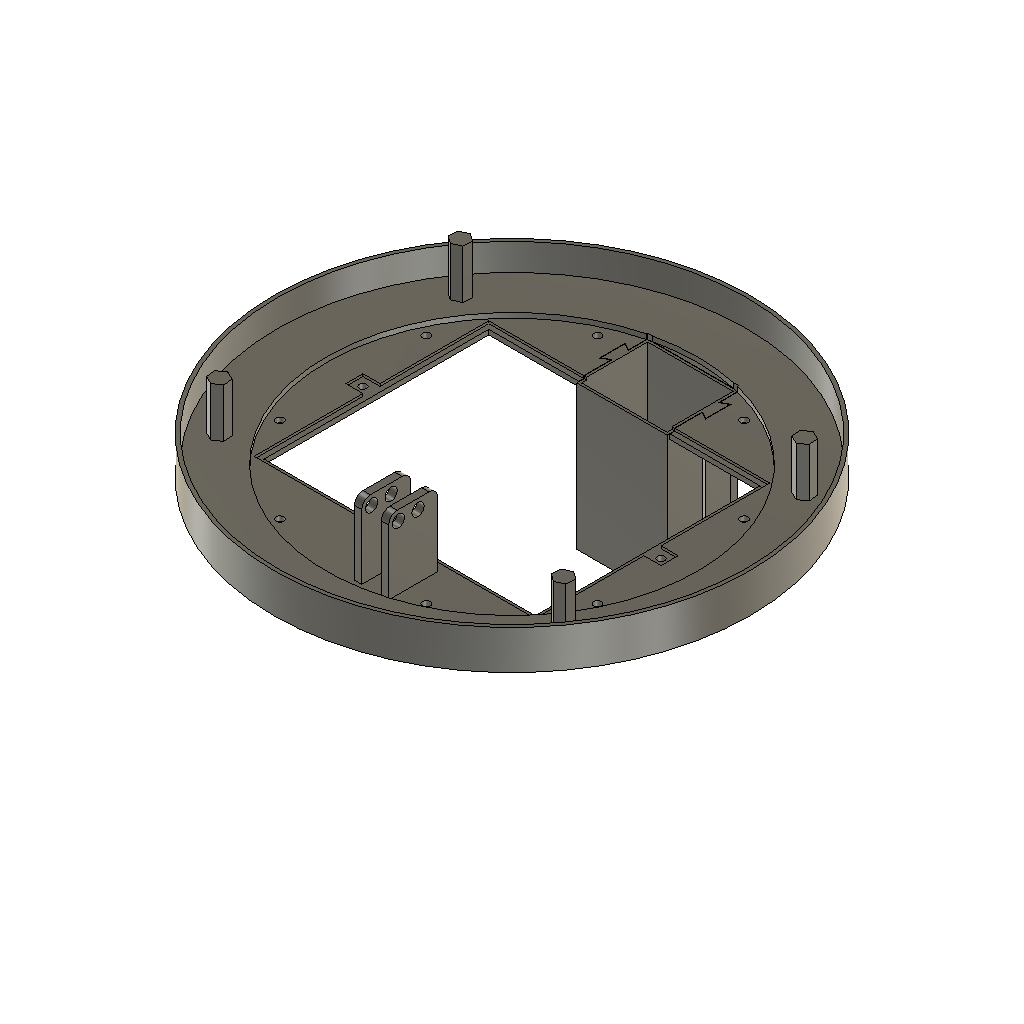
meio soccer (Autodesk Fusion 360 design; units mm, degrees)
part number: 2026-09-15-19-02-09-718
Autodesk Fusion 360 part; units mm, degrees
sketch "Esboço1" plane through (0, 0, 0) normal (0, 0, 1) x (1, 0, 0)
  circle A0 centre (0, 0) radius 97.5
  circle A1 centre (0, 0) radius 96
  circle A2 centre (0, 0) radius 76
  circle A3 centre (0, 0) radius 74.25
  dimension "d1" = 195
  dimension "d2" = 192
  dimension "d3" = 152
  dimension "d4" = 148.5
  constraint coincident A0.centre A1.centre
  constraint concentric A0 A2
  constraint concentric A0 A3
  measures "d1" diameter of A0
  measures "d2" diameter of A1
  measures "d3" diameter of A2
  measures "d4" diameter of A3
extrude "Extrusão1" add sketch "Esboço1" along normal blind 3 contours A0 | A1 | A2 | A3 makes body 1
sketch "Esboço2" plane through (0, 0, 3) normal (0, 0, 1) x (-1, 0, 0)
  circle A0 centre (0, 0) radius 97.5
  circle A1 centre (0, 0) radius 96
  dimension "d24" = 192
  constraint concentric A0 A1
  measures "d24" diameter of A1
extrude "Extrusão2" add sketch "Esboço2" along normal blind 10 bodies 1
sketch "Esboço3" plane through (0, 0, 3) normal (0, 0, 1) x (-1, 0, 0)
  circle A0 centre (0, 0) radius 96
  circle A1 centre (0, 0) radius 75.9595
  circle A2 centre (0, 0) radius 74.25
  dimension "d27" = 151.919
  dimension "d28" = 148.5
  constraint coincident A0.centre A1.centre
  constraint concentric A1 A2
  measures "d27" diameter of A1
  measures "d28" diameter of A2
extrude "Extrusão3" add sketch "Esboço3" along normal blind 10 contours A1 bodies 1
extrude "Extrusão4" add 1 faces at (-88.6796, 8.5431, 3) along direction (0, 0, 1) blind 2 on bodies 1 bodies 1
extrude "Extrusão5" cut 2 faces at (72.8824, 18.5321, 13) (-96.2796, 9.6132, 13) along direction (0, 0, -1) blind 2 on bodies 1 bodies 1
sketch "Esboço8" plane through (0, 0, 3) normal (0, 0, 1) x (-1, 0, 0)
  circle A0 centre (0, 0) radius 74.25
  line L0 (-26, -20.5) -> (26, -20.5)
  line L1 (26, -20.5) -> (26, -62.5)
  line L2 (26, -62.5) -> (-26, -62.5)
  line L3 (-26, -62.5) -> (-26, -20.5)
  dimension "d111" = 52
  dimension "d112" = 42
  constraint horizontal L0
  constraint vertical L1
  constraint horizontal L2
  constraint vertical L3
  measures "d111" distance of L0.start L0.end
  measures "d112" distance of L0.start L2.end
sketch "Esboço9" plane through (0, 0, 3) normal (0, 0, 1) x (-1, 0, 0)
  circle A0 centre (0, 0) radius 74.25
sketch "Esboço13" plane through (0, 0, 0) normal (0, 0, -1) x (1, 0, 0)
  circle A0 centre (0, 0) radius 97.5
  circle A1 centre (-30, 65) radius 1.6
  circle A2 centre (30, 65) radius 1.6
  line L0 (51, -4.42) -> (-51, -4.42)
  line L1 (-51, -4.42) -> (-51, 5.58)
  line L2 (-51, 5.58) -> (51, 5.58)
  line L3 (51, 5.58) -> (51, -4.42)
  line L4 (27.6906, 69) -> (25.3812, 65)
  line L5 (25.3812, 65) -> (27.6906, 61)
  line L6 (27.6906, 61) -> (32.3094, 61)
  line L7 (32.3094, 61) -> (34.6188, 65)
  line L8 (34.6188, 65) -> (32.3094, 69)
  line L9 (32.3094, 69) -> (27.6906, 69)
  line L10 (-32.3094, 69) -> (-34.6188, 65)
  line L11 (-34.6188, 65) -> (-32.3094, 61)
  line L12 (-32.3094, 61) -> (-27.6906, 61)
  line L13 (-27.6906, 61) -> (-25.3812, 65)
  line L14 (-25.3812, 65) -> (-27.6906, 69)
  line L15 (-27.6906, 69) -> (-32.3094, 69)
  line L16 (-61, 27.6906) -> (-61, 32.3094)
  line L17 (-69, 27.6906) -> (-65, 25.3812)
  circle A3 centre (-65, 30) radius 1.6
  line L18 (-61, 32.3094) -> (-65, 34.6188)
  line L19 (-65, 25.3812) -> (-61, 27.6906)
  line L20 (-65, 34.6188) -> (-69, 32.3094)
  line L21 (-69, 32.3094) -> (-69, 27.6906)
  line L22 (-65, -25.3812) -> (-69, -27.6906)
  line L23 (-61, -27.6906) -> (-65, -25.3812)
  line L24 (-61, -32.3094) -> (-61, -27.6906)
  line L25 (-69, -32.3094) -> (-65, -34.6188)
  circle A4 centre (-65, -30) radius 1.6
  line L26 (-69, -27.6906) -> (-69, -32.3094)
  line L27 (-65, -34.6188) -> (-61, -32.3094)
  line L28 (-27.6906, -61) -> (-32.3094, -61)
  line L29 (-27.6906, -69) -> (-25.3812, -65)
  circle A5 centre (-30, -65) radius 1.6
  line L30 (-32.3094, -61) -> (-34.6188, -65)
  line L31 (-25.3812, -65) -> (-27.6906, -61)
  line L32 (-34.6188, -65) -> (-32.3094, -69)
  line L33 (-32.3094, -69) -> (-27.6906, -69)
  line L34 (25.3812, -65) -> (27.6906, -69)
  line L35 (27.6906, -61) -> (25.3812, -65)
  line L36 (32.3094, -61) -> (27.6906, -61)
  line L37 (32.3094, -69) -> (34.6188, -65)
  circle A6 centre (30, -65) radius 1.6
  line L38 (27.6906, -69) -> (32.3094, -69)
  line L39 (34.6188, -65) -> (32.3094, -61)
  line L40 (61, -27.6906) -> (61, -32.3094)
  line L41 (69, -27.6906) -> (65, -25.3812)
  circle A7 centre (65, -30) radius 1.6
  line L42 (61, -32.3094) -> (65, -34.6188)
  line L43 (65, -25.3812) -> (61, -27.6906)
  line L44 (65, -34.6188) -> (69, -32.3094)
  line L45 (69, -32.3094) -> (69, -27.6906)
  line L46 (65, 25.3812) -> (69, 27.6906)
  line L47 (61, 27.6906) -> (65, 25.3812)
  line L48 (61, 32.3094) -> (61, 27.6906)
  line L49 (69, 32.3094) -> (65, 34.6188)
  circle A8 centre (65, 30) radius 1.6
  line L50 (69, 27.6906) -> (69, 32.3094)
  line L51 (65, 34.6188) -> (61, 32.3094)
  point P0 (30, 65)
  point P1 (30, 65)
  point P2 (30, 65)
  point P3 (-30, 65)
  point P4 (-30, 65)
  point P5 (-65, 30)
  point P6 (-65, 30)
  point P7 (-65, 30)
  point P8 (-65, -30)
  point P9 (-65, -30)
  point P10 (-30, -65)
  point P11 (-30, -65)
  point P12 (-30, -65)
  point P13 (30, -65)
  point P14 (30, -65)
  point P15 (65, -30)
  point P16 (65, -30)
  point P17 (65, -30)
  point P18 (65, 30)
  point P19 (65, 30)
  dimension "d163" = 3.2
  dimension "d164" = 3.2
  dimension "d165" = 102
  dimension "d166" = 10
  dimension "d167" = 51
  dimension "d168" = 51
  dimension "d172" = 65
  dimension "d173" = 60
  dimension "d175" = 4
  dimension "d176" = 4
  dimension "d178" = 360
  constraint horizontal L0
  constraint vertical L1
  constraint horizontal L2
  constraint vertical L3
  constraint coincident P2 P1
  constraint coincident P4 P3
  measures "d163" diameter of A1
  measures "d164" diameter of A2
  measures "d165" distance of L0.start L0.end
  measures "d166" distance of L0.start L2.end
  measures "d167" distance of A0.centre L1
  measures "d168" distance of A0.centre L3
  measures "d172" vertical distance of A0.centre P4
  measures "d173" distance of P4 P1
  measures "d175" distance of P2 L9
  measures "d176" distance of P4 L15
extrude "Extrusão14" cut sketch "Esboço13" against normal blind 1 contours L4 L5 L6 L7 L8 L9 | L10 L11 L12 L13 L14 L15 | L16 L17 L18 L19 L20 L21 | L22 L23 L24 L25 L26 L27 | L28 L29 L30 L31 L32 L33 | L34 L35 L36 L37 L38 L39 | L40 L41 L42 L43 L44 L45 | L46 L47 L48 L49 L50 L51 bodies 1
extrude "Extrusão15" cut 8 faces at (64.6384, -29.1944, 0) (30.1948, -64.5727, 0) (-30.2667, -64.861, 0) (-65.4147, -30.52, 0) (-64.6384, 29.1944, 0) (-29.9601, 64.931, 0) (29.8052, 65.4273, 0) (64.6384, 30.8056, 0) along direction (0, 0, 1) blind 45 on bodies 1 bodies 1
sketch "Esboço14" plane through (0, 0, 5) normal (0, 0, 1) x (-1, 0, 0)
  circle A0 centre (0, 0) radius 96
  circle A1 centre (0, 0) radius 75.9595
  circle A2 centre (0, 0) radius 87.5
  circle A3 centre (0, 0) radius 82.5
  line L0 (76.0946, 31.8726) -> (80.7064, 33.8042)
  line L1 (76.0946, -31.8726) -> (80.7064, -33.8042)
  line L2 (65.6498, 49.9636) -> (69.6285, 52.9917)
  line L3 (-65.6498, 49.9636) -> (-69.6285, 52.9917)
  line L4 (-10.4448, 81.8361) -> (-11.0779, 86.7959)
  line L5 (-10.4448, -81.8361) -> (-11.0779, -86.7959)
  line L6 (-65.6498, -49.9636) -> (-69.6285, -52.9917)
  line L7 (10.4448, 81.8361) -> (11.0779, 86.7959)
  line L8 (-76.0946, -31.8726) -> (-80.7064, -33.8042)
  line L9 (-76.0946, 31.8726) -> (-80.7064, 33.8042)
  line L10 (65.6498, -49.9636) -> (69.6285, -52.9917)
  line L11 (10.4448, -81.8361) -> (11.0779, -86.7959)
  dimension "d183" = 175
  dimension "d184" = 165
  dimension "d189" = 360
  dimension "d192" = 360
  constraint coincident A0.centre A1.centre
  constraint coincident A3 L0.start
  constraint coincident A2 L0.end
  constraint perpendicular A2 L0
  constraint coincident A3 L1.start
  constraint coincident A2 L1.end
  constraint perpendicular A2 L1
  constraint coincident A3 L2.start
  constraint coincident A2 L2.end
  constraint perpendicular A2 L2
  constraint coincident A3 L7.start
  constraint coincident A2 L7.end
  constraint perpendicular A2 L7
  measures "d183" diameter of A2
  measures "d184" diameter of A3
sketch "Esboço15" plane through (0, 0, 5) normal (0, 0, 1) x (-1, 0, 0)
  circle A0 centre (0, 0) radius 75.9595
  circle A1 centre (0, 0) radius 96
  line L0 (0, 0) -> (0, 110)
  line L1 (0, 110) -> (0, 0)
  line L2 (0, 0) -> (101.4671, 71.048)
  circle A2 centre (0, 0) radius 86
  line L3 (73.5599, 51.5072) -> (70.1159, 53.1131)
  line L4 (70.1159, 53.1131) -> (67.0031, 50.9335)
  line L5 (67.0031, 50.9335) -> (67.3343, 47.148)
  line L6 (67.3343, 47.148) -> (70.7783, 45.542)
  line L7 (70.7783, 45.542) -> (73.891, 47.7216)
  line L8 (73.891, 47.7216) -> (73.5599, 51.5072)
  line L9 (0, 0) -> (-94.4768, 66.1533)
  line L10 (0, 0) -> (-97.6365, -68.3658)
  line L11 (0, 0) -> (97.99, -68.6133)
  line L12 (0, 0) -> (0, -120)
  line L13 (67.3343, -47.148) -> (67.0031, -50.9335)
  line L14 (67.0031, -50.9335) -> (70.1159, -53.1131)
  line L15 (70.1159, -53.1131) -> (73.5599, -51.5072)
  line L16 (73.5599, -51.5072) -> (73.891, -47.7216)
  line L17 (73.891, -47.7216) -> (70.7783, -45.542)
  line L18 (70.7783, -45.542) -> (67.3343, -47.148)
  line L19 (-67.3343, -47.148) -> (-70.7783, -45.542)
  line L20 (-70.7783, -45.542) -> (-73.891, -47.7216)
  line L21 (-73.891, -47.7216) -> (-73.5599, -51.5072)
  line L22 (-73.5599, -51.5072) -> (-70.1159, -53.1131)
  line L23 (-70.1159, -53.1131) -> (-67.0031, -50.9335)
  line L24 (-67.0031, -50.9335) -> (-67.3343, -47.148)
  line L25 (-67.3343, 47.148) -> (-67.0031, 50.9335)
  line L26 (-67.0031, 50.9335) -> (-70.1159, 53.1131)
  line L27 (-70.1159, 53.1131) -> (-73.5599, 51.5072)
  line L28 (-73.5599, 51.5072) -> (-73.891, 47.7216)
  line L29 (-73.891, 47.7216) -> (-70.7783, 45.542)
  line L30 (-70.7783, 45.542) -> (-67.3343, 47.148)
  point P0 (70.4471, 49.3276)
  point P1 (70.4471, -49.3276)
  point P2 (-70.4471, -49.3276)
  point P3 (-70.4471, 49.3276)
  dimension "d195" = 55
  dimension "d196" = 172
  dimension "d197" = 3.8
  dimension "d198" = 55
  dimension "d199" = 55
  dimension "d200" = 55
  dimension "d201" = 3.8
  dimension "d202" = 3.8
  dimension "d203" = 3.8
  constraint coincident A0.centre A1.centre
  constraint vertical L0
  constraint coincident A2 P0
  constraint coincident L2 P0
  constraint coincident L2 L3.start
  constraint vertical L12
  constraint coincident L11 P1
  constraint coincident A2 P1
  constraint coincident A2 P2
  constraint coincident L10 P2
  constraint coincident A2 P3
  constraint coincident L9 P3
  measures "d195" angle of L0 L2
  measures "d196" diameter of A2
  measures "d197" distance of L3.start P0
  measures "d198" angle of L1 L9
  measures "d199" angle of L11 L12
  measures "d200" angle of L10 L12
  measures "d201" distance of L13.start P1
  measures "d202" distance of L19.start P2
  measures "d203" distance of L25.start P3
extrude "Extrusão17" add sketch "Esboço15" along normal blind 20 contours L2 A2 L4 L5 | L2 A2 L6 L7 | A2 L11 L17 L18 | A2 L11 L13 L14 | L2 A2 L3 L4 | L2 A2 L7 L8 | A2 L11 L14 L15 | A2 L11 L16 L17 | A2 L9 L29 L30 | A2 L9 L25 L26 | A2 L9 L26 L27 | A2 L10 L23 L24 | A2 L10 L19 L20 | A2 L10 L22 L23 | A2 L9 L28 L29 | A2 L10 L20 L21 bodies 1
extrude "Extrusão18" cut 1 faces at (72.8824, 18.5321, 11) along direction (0, 0, -1) blind 8 on bodies 1 bodies 1
sketch "Esboço38" plane through (0, 0, 3) normal (0, 0, 1) x (-1, 0, 0)
  line L0 (57.5, -48) -> (-57.5, -48)
  line L1 (-57.5, -48) -> (-57.5, 48)
  line L2 (-57.5, 48) -> (57.5, 48)
  line L3 (57.5, 48) -> (57.5, -48)
  line L4 (3.5, -48) -> (-3.5, -48)
  line L5 (-3.5, -48) -> (-3.5, -55)
  line L6 (-3.5, -55) -> (3.5, -55)
  line L7 (3.5, -55) -> (3.5, -48)
  circle A0 centre (0, -51.5) radius 1.5
  line L8 (-57.5, -3.5) -> (-64.5, -3.5)
  line L9 (-64.5, -3.5) -> (-64.5, 3.5)
  line L10 (-64.5, 3.5) -> (-57.5, 3.5)
  line L11 (-57.5, 3.5) -> (-57.5, -3.5)
  circle A1 centre (-61, 0) radius 1.5
  line L12 (3.5, 48) -> (3.5, 55)
  line L13 (3.5, 55) -> (-3.5, 55)
  line L14 (-3.5, 55) -> (-3.5, 48)
  line L15 (64.5, 3.5) -> (64.5, -3.5)
  line L16 (57.5, 3.5) -> (64.5, 3.5)
  line L17 (64.5, -3.5) -> (57.5, -3.5)
  dimension "d453" = 115
  dimension "d454" = 96
  dimension "d455" = 57.5
  dimension "d456" = 57.5
  dimension "d457" = 48
  dimension "d458" = 48
  dimension "d459" = 7
  dimension "d460" = 7
  dimension "d462" = 3
  dimension "d463" = 3.5
  dimension "d464" = 7
  dimension "d465" = 7
  dimension "d466" = 7
  dimension "d468" = 3
  dimension "d469" = 3.5
  dimension "d471" = 360
  dimension "d476" = 44.5
  constraint horizontal L0
  constraint vertical L1
  constraint horizontal L2
  constraint vertical L3
  constraint horizontal L4
  constraint vertical L5
  constraint horizontal L6
  constraint vertical L7
  constraint coincident L0 L4.start
  constraint horizontal L8
  constraint vertical L9
  constraint horizontal L10
  constraint vertical L11
  constraint coincident L1 L8.start
  measures "d453" distance of L0.start L0.end
  measures "d454" distance of L0.start L2.end
  measures "d455" distance of origin L3
  measures "d456" distance of origin L1
  measures "d457" distance of origin L0
  measures "d458" distance of origin L2
  measures "d459" distance of L4.start L4.end
  measures "d460" distance of L4.start L6.end
  measures "d462" diameter of A0
  measures "d463" distance of L0 A0.centre
  measures "d464" distance of L8.end L9.end
  measures "d465" distance of L9.end L10.end
  measures "d466" distance of L8.start L8.end
  measures "d468" diameter of A1
  measures "d469" distance of L1 A1.centre
  measures "d476" distance of L2 L10
sketch "Esboço39" plane through (0, 0, 3) normal (0, 0, 1) x (-1, 0, 0)
  line L0 (-57.5, 48) -> (57.5, 48)
  line L1 (57.5, 48) -> (57.5, -48)
  circle A0 centre (0, 51.5) radius 1.5
  line L2 (-3.5, 55) -> (-3.5, 48)
  circle A1 centre (61, 0) radius 1.5
  line L3 (57.5, 3.5) -> (64.5, 3.5)
  dimension "d477" = 3
  dimension "d478" = 3.5
  dimension "d479" = 3.5
  dimension "d480" = 3
  dimension "d481" = 3.5
  dimension "d482" = 3.5
  measures "d477" diameter of A0
  measures "d478" distance of L0 A0.centre
  measures "d479" distance of A0.centre L2
  measures "d480" diameter of A1
  measures "d481" distance of A1.centre L3
  measures "d482" distance of L1 A1.centre
extrude "Extrusão42" cut sketch "Esboço39" against normal blind 10 bodies 1
extrude "Extrusão43" cut sketch "Esboço38" against normal blind 10 contours A0 | A1 bodies 1
extrude "Extrusão44" cut sketch "Esboço38" against normal blind 5 contours L0 L1 L2 L3 L4 L11 bodies 1
extrude "Extrusão45" cut sketch "Esboço38" against normal blind 1 contours L0 L4 L5 L6 L7 | L3 L15 L16 L17 | L1 L8 L9 L10 L11 | L2 L12 L13 L14 bodies 1
extrude "Extrusão46" add 1 faces at (-96.2796, 9.6132, 11) along direction (0, 0, 1) blind 5 on bodies 1 bodies 1
sketch "Esboço40" plane through (0, 0, 0) normal (0, 0, -1) x (1, 0, 0)
  circle A0 centre (61, 0) radius 1.5
  circle A1 centre (0, -51.5) radius 1.5
  line L0 (-25.3812, -65) -> (-27.6906, -69)
  line L1 (-27.6906, -69) -> (-32.3094, -69)
  line L2 (-32.3094, -69) -> (-34.6188, -65)
  line L3 (-34.6188, -65) -> (-32.3094, -61)
  line L4 (-32.3094, -61) -> (-27.6906, -61)
  line L5 (-27.6906, -61) -> (-25.3812, -65)
  line L6 (-34.6188, 65) -> (-32.3094, 69)
  line L7 (-32.3094, 69) -> (-27.6906, 69)
  line L8 (-27.6906, 69) -> (-25.3812, 65)
  line L9 (-25.3812, 65) -> (-27.6906, 61)
  line L10 (-27.6906, 61) -> (-32.3094, 61)
  line L11 (-32.3094, 61) -> (-34.6188, 65)
  line L12 (25.3812, 65) -> (27.6906, 69)
  line L13 (27.6906, 69) -> (32.3094, 69)
  line L14 (32.3094, 69) -> (34.6188, 65)
  line L15 (34.6188, 65) -> (32.3094, 61)
  line L16 (32.3094, 61) -> (27.6906, 61)
  line L17 (27.6906, 61) -> (25.3812, 65)
  line L18 (27.6906, -61) -> (32.3094, -61)
  line L19 (32.3094, -61) -> (34.6188, -65)
  line L20 (34.6188, -65) -> (32.3094, -69)
  line L21 (32.3094, -69) -> (27.6906, -69)
  line L22 (27.6906, -69) -> (25.3812, -65)
  line L23 (25.3812, -65) -> (27.6906, -61)
  line L24 (-61, -27.6906) -> (-61, -32.3094)
  line L25 (-61, -32.3094) -> (-65, -34.6188)
  line L26 (-65, -34.6188) -> (-69, -32.3094)
  line L27 (-69, -32.3094) -> (-69, -27.6906)
  line L28 (-69, -27.6906) -> (-65, -25.3812)
  line L29 (-65, -25.3812) -> (-61, -27.6906)
  line L30 (-65, 25.3812) -> (-69, 27.6906)
  line L31 (-69, 27.6906) -> (-69, 32.3094)
  line L32 (-69, 32.3094) -> (-65, 34.6188)
  line L33 (-65, 34.6188) -> (-61, 32.3094)
  line L34 (-61, 32.3094) -> (-61, 27.6906)
  line L35 (-61, 27.6906) -> (-65, 25.3812)
  line L36 (61, 27.6906) -> (61, 32.3094)
  line L37 (61, 32.3094) -> (65, 34.6188)
  line L38 (65, 34.6188) -> (69, 32.3094)
  line L39 (69, 32.3094) -> (69, 27.6906)
  line L40 (69, 27.6906) -> (65, 25.3812)
  line L41 (65, 25.3812) -> (61, 27.6906)
  line L42 (65, -25.3812) -> (69, -27.6906)
  line L43 (69, -27.6906) -> (69, -32.3094)
  line L44 (69, -32.3094) -> (65, -34.6188)
  line L45 (65, -34.6188) -> (61, -32.3094)
  line L46 (61, -32.3094) -> (61, -27.6906)
  line L47 (61, -27.6906) -> (65, -25.3812)
  circle A2 centre (0, 0) radius 97.5
  circle A3 centre (-61, 0) radius 1.5
  circle A4 centre (0, 51.5) radius 1.5
  line L48 (57.5, -48) -> (-57.5, -48)
  line L49 (-57.5, -48) -> (-57.5, 48)
  line L50 (-57.5, 48) -> (57.5, 48)
  line L51 (57.5, 48) -> (57.5, -48)
  line L52 (-55.5, 46) -> (55.5, 46)
  line L53 (55.5, 46) -> (55.5, -46)
  line L54 (55.5, -46) -> (-55.5, -46)
  line L55 (-55.5, -46) -> (-55.5, 46)
  line L56 (57.5, -48) -> (57.5, 48)
  line L57 (-57.5, 48) -> (-57.5, -48)
  line L58 (57.5, 48) -> (-57.5, 48)
  line L59 (-57.5, -48) -> (57.5, -48)
  dimension "d493" = 2
  dimension "d494" = 2
  dimension "d495" = 2
  dimension "d496" = 2
  constraint horizontal L52
  constraint vertical L53
  constraint horizontal L54
  constraint vertical L55
  measures "d493" distance of L53 L56
  measures "d494" distance of L55 L57
  measures "d495" distance of L52 L58
  measures "d496" distance of L54 L59
extrude "Extrusão47" add sketch "Esboço40" against normal blind 2 contours L48 L49 L50 L51 L56 L57 L58 L59 bodies 1
sketch "Esboço41" plane through (0, 0, 3) normal (0, 0, 1) x (-1, 0, 0)
  circle A0 centre (0, 0) radius 75.9595
  circle A1 centre (-65, -30) radius 1.6
  circle A2 centre (30, -65) radius 1.6
  circle A3 centre (65, 30) radius 1.6
  circle A4 centre (-30, 65) radius 1.6
  circle A5 centre (-65, 30) radius 1.6
  circle A6 centre (30, 65) radius 1.6
  circle A7 centre (65, -30) radius 1.6
  circle A8 centre (-30, -65) radius 1.6
  line L0 (-3.5, 48) -> (-3.5, 55)
  line L1 (-3.5, 55) -> (3.5, 55)
  line L2 (3.5, 55) -> (3.5, 48)
  line L3 (3.5, 48) -> (57.5, 48)
  line L4 (57.5, 48) -> (57.5, 3.5)
  line L5 (57.5, 3.5) -> (64.5, 3.5)
  line L6 (64.5, 3.5) -> (64.5, -3.5)
  line L7 (64.5, -3.5) -> (57.5, -3.5)
  line L8 (57.5, -3.5) -> (57.5, -48)
  line L9 (57.5, -48) -> (3.5, -48)
  line L10 (3.5, -48) -> (3.5, -55)
  line L11 (3.5, -55) -> (-3.5, -55)
  line L12 (-3.5, -55) -> (-3.5, -48)
  line L13 (-3.5, -48) -> (-57.5, -48)
  line L14 (-57.5, -48) -> (-57.5, -3.5)
  line L15 (-57.5, -3.5) -> (-64.5, -3.5)
  line L16 (-64.5, -3.5) -> (-64.5, 3.5)
  line L17 (-64.5, 3.5) -> (-57.5, 3.5)
  line L18 (-57.5, 3.5) -> (-57.5, 48)
  line L19 (-57.5, 48) -> (-3.5, 48)
  line L20 (-18.5, -74) -> (18.5, -74)
  line L21 (18.5, -74) -> (18.5, -18)
  line L22 (18.5, -18) -> (-18.5, -18)
  line L23 (-18.5, -18) -> (-18.5, -74)
  line L24 (-18.5, -74) -> (18.5, -18) construction
  line L25 (18.5, -74) -> (-18.5, -18) construction
  line L26 (18.5, -66) -> (21.5, -67.7321)
  line L27 (21.5, -67.7321) -> (21.5, -57.7321)
  line L28 (21.5, -57.7321) -> (18.5, -59.4641)
  line L29 (-18.5, -66) -> (-21.5, -67.7321)
  line L30 (-21.5, -67.7321) -> (-21.5, -57.7321)
  line L31 (-21.5, -57.7321) -> (-18.5, -59.4641)
  line L32 (55.5, -46) -> (-55.5, -46)
  line L33 (18.65, -74.15) -> (-18.65, -74.15)
  line L34 (-18.65, -74.15) -> (-18.65, -66.2598)
  line L35 (-18.65, -66.2598) -> (-21.65, -67.9919)
  line L36 (-21.65, -67.9919) -> (-21.65, -57.4722)
  line L37 (-21.65, -57.4722) -> (-18.65, -59.2043)
  line L38 (-18.65, -59.2043) -> (-18.65, -46)
  line L39 (-18.65, -46) -> (18.65, -46)
  line L40 (18.65, -59.2043) -> (21.65, -57.4722)
  line L41 (21.65, -57.4722) -> (21.65, -67.9919)
  line L42 (21.65, -67.9919) -> (18.65, -66.2598)
  line L43 (18.65, -66.2598) -> (18.65, -74.15)
  line L44 (18.65, -59.2043) -> (18.65, -46)
  line L45 (17.5, -73) -> (-17.5, -73)
  line L46 (-17.5, -73) -> (-17.5, -46)
  line L47 (-17.5, -46) -> (17.5, -46)
  line L48 (17.5, -46) -> (17.5, -73)
  line L49 (18.5, -45) -> (-18.5, -45)
  point P0 (0, -46)
  dimension "d499" = 37
  dimension "d500" = 56
  dimension "d501" = 10
  dimension "d502" = 10
  dimension "d503" = 8
  dimension "d505" = 3
  dimension "d506" = 60
  dimension "d507" = 60
  dimension "d508" = 3
  dimension "d509" = 8
  dimension "d510" = 60
  dimension "d511" = 60
  dimension "d512" = 0.15
  dimension "d513" = 0.15
  dimension "d514" = 0.15
  dimension "d515" = 0.15
  dimension "d516" = 0.15
  dimension "d517" = 0.15
  dimension "d518" = 0.15
  dimension "d519" = 0.15
  dimension "d520" = 0.15
  dimension "d521" = 0.15
  dimension "d523" = 0.15
  dimension "d530" = 1
  dimension "d531" = 1
  dimension "d532" = 1
  dimension "d533" = 27
  dimension "d536" = 1
  constraint horizontal L20
  constraint perpendicular L20 L21
  constraint parallel L20 L22
  constraint parallel L21 L23
  constraint coincident L24 P0
  constraint coincident L25 P0
  constraint coincident L21 L26.start
  constraint perpendicular L9 L27
  constraint coincident L21 L28.end
  constraint coincident L23 L29.start
  constraint parallel L23 L30
  constraint coincident L23 L31.end
  constraint coincident P0 L32
  constraint perpendicular L21 L33
  constraint perpendicular L33 L34
  constraint coincident L32 L38.end
  constraint perpendicular L32 L38
  constraint coincident L32 L39.end
  constraint perpendicular L9 L41
  constraint perpendicular L32 L44
  constraint parallel L31 L37
  constraint parallel L30 L36
  constraint parallel L29 L35
  constraint parallel L21 L43
  constraint parallel L28 L40
  constraint parallel L26 L42
  constraint midpoint P0 L32
  constraint horizontal L45
  constraint vertical L46
  constraint horizontal L47
  constraint vertical L48
  constraint coincident L21 L49.start
  constraint coincident L23 L49.end
  constraint perpendicular L23 L49
  measures "d499" distance of L21.end L22.end
  measures "d500" distance of L20.end L21.end
  measures "d501" distance of L26.end L27.end
  measures "d502" distance of L29.end L30.end
  measures "d503" distance of L20.start L29.start
  measures "d505" distance of L23 L30
  measures "d506" angle of L23 L29
  measures "d507" angle of L23 L31
  measures "d508" distance of L21 L27
  measures "d509" distance of L20 L26.start
  measures "d510" angle of L21 L26
  measures "d511" angle of L21 L28
  measures "d512" distance of L27 L41
  measures "d513" distance of L28 L40
  measures "d514" distance of L21 L44
  measures "d515" distance of L23 L38
  measures "d516" distance of L31 L37
  measures "d517" distance of L30 L36
  measures "d518" distance of L29 L35
  measures "d519" distance of L23 L34
  measures "d520" distance of L20 L33
  measures "d521" distance of L21 L43
  measures "d523" distance of L26 L42
  measures "d530" distance of L20 L45
  measures "d531" distance of L21 L48
  measures "d532" distance of L23 L46
  measures "d533" distance of L45.end L46.end
  measures "d536" distance of L39 L49
extrude "Extrusão48" cut sketch "Esboço41" against normal blind 3 contours A0 L13 L23 L29 L30 L31 L34 L35 L36 L37 L38 | A0 L20 L23 L33 L34 | A0 L20 L21 L33 L43 | A0 L9 L21 L26 L27 L28 L40 L41 L42 L43 L44 | A0 L9 L13 L20 L21 L23 L45 L46 L48 | A0 L20 L23 | A0 L20 L21 | A0 L20 L33 | L23 L29 L30 L31 | L21 L26 L27 L28 | L13 L23 L32 L39 L46 | L13 L23 L32 L38 L39 | L9 L21 L32 L39 L44 | L9 L21 L32 L39 L48 | L9 L10 L11 L12 L13 L32 L39 L46 L47 L48 | L9 L10 L11 L12 L13 L45 L46 L48 bodies 1
extrude "Extrusão49" cut sketch "Esboço41" along normal blind 6 contours A0 L20 L23 L33 L34 | A0 L20 L21 L33 L43 | A0 L20 L23 | A0 L20 L21 bodies 1
extrude "Extrusão50" add sketch "Esboço41" against normal blind 60 contours A0 L9 L13 L20 L21 L23 L45 L46 L48 | L23 L29 L30 L31 | L21 L26 L27 L28 | L13 L23 L32 L39 L46 | L9 L21 L32 L39 L48 | L21 L23 L32 L39 L47 L49 bodies 1 makes body 2
sketch "Esboço42" plane through (0, 0, 3) normal (0, 0, 1) x (-1, 0, 0)
  line L0 (-17.5, -46) -> (17.5, -46)
  line L1 (17.5, -46) -> (17.5, -73)
  line L2 (17.5, -73) -> (-17.5, -73)
  line L3 (-17.5, -73) -> (-17.5, -46)
  line L4 (-18.5, -66) -> (-18.5, -73.6722)
  arc A0 (-18.5, -73.6722) -> (-17.1419, -74) centre (0, 0) ccw
  line L5 (-17.1419, -74) -> (17.1419, -74)
  arc A1 (17.1419, -74) -> (18.5, -73.6722) centre (0, 0) ccw
  line L6 (18.5, -73.6722) -> (18.5, -66)
  line L7 (18.5, -66) -> (21.5, -67.7321)
  line L8 (21.5, -67.7321) -> (21.5, -57.7321)
  line L9 (21.5, -57.7321) -> (18.5, -59.4641)
  line L10 (18.5, -59.4641) -> (18.5, -45)
  line L11 (18.5, -45) -> (-18.5, -45)
  line L12 (-18.5, -45) -> (-18.5, -59.4641)
  line L13 (-18.5, -59.4641) -> (-21.5, -57.7321)
  line L14 (-21.5, -57.7321) -> (-21.5, -67.7321)
  line L15 (-21.5, -67.7321) -> (-18.5, -66)
  line L16 (18.5, -45) -> (-18.5, -45)
  line L17 (-18.5, -45) -> (-18.5, -47.9888)
  line L18 (-18.5, -47.9888) -> (18.5, -47.9888)
  line L19 (18.5, -47.9888) -> (18.5, -45)
  constraint horizontal L16
  constraint vertical L17
  constraint horizontal L18
  constraint vertical L19
  constraint coincident L12 L17.end
  constraint coincident L10.end L11.start
extrude "Extrusão51" cut sketch "Esboço42" against normal blind 1 contours L0 L1 L3 L10 L11 L12 L16 L17 L18 L19 bodies 2
sketch "Esboço43" plane through (0, 0, 3) normal (0, 0, 1) x (-1, 0, 0)
  line L0 (-18.65, -59.2043) -> (-18.65, -48)
  line L1 (-18.65, -48) -> (-57.5, -48)
  line L2 (-57.5, -48) -> (-57.5, -3.5)
  line L3 (-57.5, -3.5) -> (-64.5, -3.5)
  line L4 (-64.5, -3.5) -> (-64.5, 3.5)
  line L5 (-64.5, 3.5) -> (-57.5, 3.5)
  line L6 (-57.5, 3.5) -> (-57.5, 48)
  line L7 (-57.5, 48) -> (-3.5, 48)
  line L8 (-3.5, 48) -> (-3.5, 55)
  line L9 (-3.5, 55) -> (3.5, 55)
  line L10 (3.5, 55) -> (3.5, 48)
  line L11 (3.5, 48) -> (57.5, 48)
  line L12 (57.5, 48) -> (57.5, 3.5)
  line L13 (57.5, 3.5) -> (64.5, 3.5)
  line L14 (64.5, 3.5) -> (64.5, -3.5)
  line L15 (64.5, -3.5) -> (57.5, -3.5)
  line L16 (57.5, -3.5) -> (57.5, -48)
  line L17 (57.5, -48) -> (18.65, -48)
  line L18 (18.65, -48) -> (18.65, -59.2043)
  line L19 (18.65, -59.2043) -> (21.65, -57.4722)
  line L20 (21.65, -57.4722) -> (21.65, -67.9919)
  line L21 (21.65, -67.9919) -> (18.65, -66.2598)
  line L22 (18.65, -66.2598) -> (18.65, -73.6344)
  arc A0 (18.65, -73.6344) -> (-18.65, -73.6344) centre (0, 0) ccw
  line L23 (-18.65, -73.6344) -> (-18.65, -66.2598)
  line L24 (-18.65, -66.2598) -> (-21.65, -67.9919)
  line L25 (-21.65, -67.9919) -> (-21.65, -57.4722)
  line L26 (-21.65, -57.4722) -> (-18.65, -59.2043)
  circle A1 centre (-30, -65) radius 1.6
  circle A2 centre (65, -30) radius 1.6
  circle A3 centre (30, 65) radius 1.6
  circle A4 centre (-65, 30) radius 1.6
  circle A5 centre (-30, 65) radius 1.6
  circle A6 centre (65, 30) radius 1.6
  circle A7 centre (30, -65) radius 1.6
  circle A8 centre (-65, -30) radius 1.6
  line L27 (-6.9213, 51.389) -> (-9.9213, 51.389)
  line L28 (-9.9213, 51.389) -> (-9.9213, 71.389)
  line L29 (-9.9213, 71.389) -> (-6.9213, 71.389)
  line L30 (-6.9213, 71.389) -> (-6.9213, 51.389)
  line L31 (-9.9213, 51.389) -> (-17.9213, 51.389)
  line L32 (-17.9213, 51.389) -> (-17.9213, 71.389)
  line L33 (-17.9213, 71.389) -> (-9.9213, 71.389)
  line L34 (-9.9213, 71.389) -> (-9.9213, 51.389)
  line L35 (-17.9213, 51.389) -> (-20.9213, 51.389)
  line L36 (-20.9213, 51.389) -> (-20.9213, 71.389)
  line L37 (-20.9213, 71.389) -> (-17.9213, 71.389)
  line L38 (-17.9213, 71.389) -> (-17.9213, 51.389)
  dimension "d541" = 3
  dimension "d542" = 3
  dimension "d543" = 8
  dimension "d544" = 20
  dimension "d545" = 20
  dimension "d546" = 20
  constraint horizontal L27
  constraint vertical L28
  constraint horizontal L29
  constraint vertical L30
  constraint horizontal L31
  constraint vertical L32
  constraint horizontal L33
  constraint vertical L34
  constraint horizontal L35
  constraint vertical L36
  constraint horizontal L37
  constraint vertical L38
  measures "d541" distance of L27.start L27.end
  measures "d542" distance of L31.end L35.end
  measures "d543" distance of L32.end L28.end
  measures "d544" distance of L27.start L29.end
  measures "d545" distance of L35.end L36.end
  measures "d546" distance of L31 L33
extrude "Extrusão52" add sketch "Esboço43" along normal blind 30 contours L27 L28 L29 L30 L34 | L32 L35 L36 L37 L38 bodies 1
sketch "Esboço44" plane through (6.9213, 0, 0) normal (-1, 0, 0) x (0, -1, 0)
  line L0 (51.389, 3) -> (71.389, 3)
  line L1 (71.389, 3) -> (71.389, 33)
  line L2 (71.389, 33) -> (51.389, 33)
  line L3 (51.389, 33) -> (51.389, 3)
  circle A0 centre (67.389, 29) radius 2.5
  circle A1 centre (59.389, 29) radius 2.5
  dimension "d549" = 5
  dimension "d550" = 5
  dimension "d551" = 8
  dimension "d552" = 4
  dimension "d553" = 4
  measures "d549" diameter of A0
  measures "d550" diameter of A1
  measures "d551" distance of A0.centre A1.centre
  measures "d552" distance of L2 A0.centre
  measures "d553" distance of L1 A0.centre
extrude "Extrusão53" cut sketch "Esboço44" against normal blind 19 contours A0 | A1 bodies 1
fillet "Arredondamento1" radius 3.5 4 edges at (8.4213, -71.389, 33) (19.4213, -71.389, 33) (8.4213, -51.389, 33) (19.4213, -51.389, 33) on bodies 1
